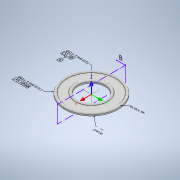
# Autodesk Inventor part: nist_ftc_11_asme1
Saved by Autodesk Inventor 2021 (Build 250183000, 183)
## iProperties
Created: 2016-11-30
Part Number: nist_ftc_11_asme1
Material: Generic
Document SubType Name: Modeling
Designer: t_liuje
Density: 1 g/cm^3
Appearance: Default
Author: t_liuje
Autodesk Inventor part; units mm, degrees
ref_plane "YZ Plane" through (0, 0, 0) normal (1, 0, 0) x (0, 1, 0)
ref_plane "XZ Plane" through (0, 0, 0) normal (0, 1, 0) x (-1, 0, 0)
sketch "Sketch1" plane through (0, 0, 0) normal (0, 1, 0) x (-1, 0, 0)
  line L0 (0, -5.0696) -> (0, 4.8633)
  line L1 (16, 0) -> (31.5, 0)
  line L2 (31.5, 0) -> (31.5, 1.5)
  arc A0 (31.5, 1.5) -> (28.5615, 1.925) centre (30, 1.5) ccw
  line L3 (16, 0) -> (16, 1.5)
  arc A1 (18.9794, 1.925) -> (16, 1.5) centre (17.52, 1.5) ccw
  line L4 (28.5615, 1.925) -> (18.9794, 1.925)
  point P0 (0, 0)
  dimension "d0" = 15.5
  dimension "d1" = 32
  dimension "d2" = 1.5
  dimension "d3" = 3
  dimension "d4" = 3.04
  dimension "d5" = 1.925
  dimension "d6" = 1.5
  constraints: 10 end point, 4 point on circle, 2 centre point, 2 horizontal, 2 point on line, 2 tangent, 2 vertical, 1 perpendicular
  measures "d0" distance of L1.start L1.end
  measures "d1" diameter of L1.start L0
  measures "d2" distance of L1.end L2.end
  measures "d3" diameter of A0
  measures "d4" diameter of A1
  measures "d5" distance between parallel lines of L1 L4
  measures "d6" distance from line of L1 A1.centre
revolve "Revolution1" add sketch "Sketch1" angle 360 about axis through (0, 0, -5.0696) along (0, 0, 1)
fillet "Fillet1" radius 0.1 2 edges at (18.9794, 0, 1.925) (28.5615, 0, 1.925)
sketch3d "3D Sketch1"
ref_plane "Work Plane1" through (0, 40, 10) normal (0, -1, 0) x (-1, 0, 0)
sketch "Sketch3" plane through (0, 40, 10) normal (0, -1, 0) x (-1, 0, 0)
  line L0 (7.2719, -7.308) -> (1.8677, -7.308) construction
  line L1 (1.8677, -7.308) -> (1.8677, -4.0655) construction
  line L2 (1.8677, -4.0655) -> (7.2719, -4.0655) construction
  line L3 (7.2719, -4.0655) -> (7.2719, -7.308) construction
  point P0 (0, 10)
  constraints: 2 other
body "Solid1"
